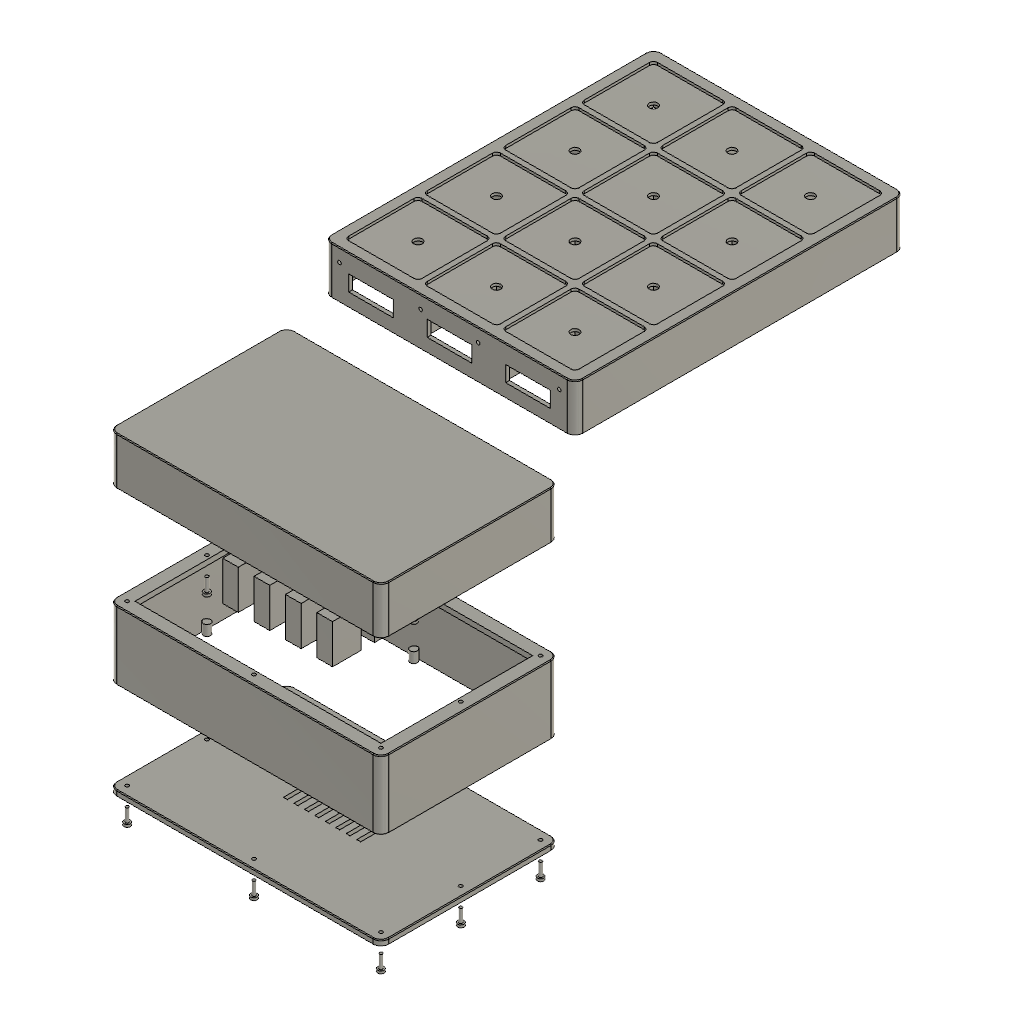
2026-11-06_BedPrototype_exploded (Autodesk Fusion 360 design; units mm, degrees)
part number: 2026-11-06-16-17-52-763
part number: 2026-11-06-16-17-53-532
part number: 2026-11-06-16-17-53-541
part number: 2026-11-06-16-17-56-764
part number: 2026-11-06-16-18-10-254
part number: 2026-11-06-16-18-27-251
part number: 2026-11-06-16-18-36-458
part number: 2026-11-06-16-18-36-601
part number: 2026-11-06-16-18-37-298
part number: 2026-11-06-16-18-38-009
part number: 2026-11-06-16-18-38-722
part number: 2026-11-06-16-18-39-449
part number: 2026-11-06-16-18-40-166
part number: 2026-11-06-16-18-41-052
part number: 2026-11-06-16-18-41-792
part number: 2026-11-06-16-18-42-542
part number: 2026-11-06-16-18-43-311
part number: 2026-11-06-16-18-44-069
part number: 2026-11-06-16-18-44-830
part number: 2026-11-06-16-18-45-611
part number: 2026-11-06-16-21-55-752
part number: 2026-11-06-16-21-56-338
part number: 2026-11-06-16-22-01-280
part number: 2026-11-06-16-22-06-008
part number: 2026-11-06-16-22-10-940
part number: 2026-11-06-16-22-16-295
part number: 2026-11-06-16-22-16-807
part number: 2026-11-06-16-22-21-639
part number: 2026-11-06-16-22-26-652
part number: 2026-11-06-16-22-31-892
part number: 2026-11-06-16-22-37-156
part number: 2026-11-06-16-22-42-135
part number: 2026-11-06-16-22-47-394
part number: 2026-11-06-16-22-53-084
part number: 2026-11-06-16-23-01-019
part number: 2026-11-06-16-23-01-608
part number: 2026-11-06-16-23-07-100
part number: 2026-11-06-16-23-12-774
part number: 2026-11-06-16-23-18-494
part number: 2026-11-06-16-23-24-293
part number: 2026-11-06-16-23-30-353
part number: 2026-11-06-16-23-36-101
part number: 2026-11-06-16-23-41-974
Autodesk Fusion 360 part; units mm, degrees
(part 1 of 3)
ref_plane "WorkPlane1" through (0, 0, 0) normal (0, 0, 1) x (1, 0, 0) in component "BedFrame_CellDeck"
sketch "DeckBlank_Sketch" plane through (0, 0, 0) normal (0, 0, 1) x (1, 0, 0) in component "BedFrame_CellDeck"
  line L0 (-96, -126) -> (96, -126)
  line L1 (96, -126) -> (96, 126)
  line L2 (96, 126) -> (-96, 126)
  line L3 (-96, 126) -> (-96, -126)
extrude "DeckBlank" add sketch "DeckBlank_Sketch" along normal blind 36 makes body 1 in component "BedFrame_CellDeck"
fillet "OuterCorner_R6" radius 6 4 edges at (-96, 126, 18) (96, 126, 18) (96, -126, 18) (-96, -126, 18) on bodies 1 in component "BedFrame_CellDeck"
ref_plane "WorkPlane2" through (0, 0, 0) normal (0, 0, 1) x (1, 0, 0) in component "BedFrame_CellDeck"
sketch "OpenUnderside_Sketch" plane through (0, 0, 0) normal (0, 0, 1) x (1, 0, 0) in component "BedFrame_CellDeck"
  line L0 (-93, -123) -> (93, -123)
  line L1 (93, -123) -> (93, 123)
  line L2 (93, 123) -> (-93, 123)
  line L3 (-93, 123) -> (-93, -123)
extrude "OpenUnderside" cut sketch "OpenUnderside_Sketch" along normal blind 32 bodies 1 in component "BedFrame_CellDeck"
ref_plane "WorkPlane3" through (0, 0, 0) normal (0, 0, 1) x (1, 0, 0) in component "BedFrame_CellDeck"
sketch "LongRib_0_Sketch" plane through (0, 0, 0) normal (0, 0, 1) x (1, 0, 0) in component "BedFrame_CellDeck"
  line L0 (-32, -123.1) -> (-28, -123.1)
  line L1 (-28, -123.1) -> (-28, 123.1)
  line L2 (-28, 123.1) -> (-32, 123.1)
  line L3 (-32, 123.1) -> (-32, -123.1)
extrude "LongRib_0" add sketch "LongRib_0_Sketch" along normal blind 32 bodies 1 in component "BedFrame_CellDeck"
ref_plane "WorkPlane4" through (0, 0, 0) normal (0, 0, 1) x (1, 0, 0) in component "BedFrame_CellDeck"
sketch "LongRib_1_Sketch" plane through (0, 0, 0) normal (0, 0, 1) x (1, 0, 0) in component "BedFrame_CellDeck"
  line L0 (28, -123.1) -> (32, -123.1)
  line L1 (32, -123.1) -> (32, 123.1)
  line L2 (32, 123.1) -> (28, 123.1)
  line L3 (28, 123.1) -> (28, -123.1)
extrude "LongRib_1" add sketch "LongRib_1_Sketch" along normal blind 32 bodies 1 in component "BedFrame_CellDeck"
ref_plane "WorkPlane5" through (0, 0, 0) normal (0, 0, 1) x (1, 0, 0) in component "BedFrame_CellDeck"
sketch "CrossRib_0_Sketch" plane through (0, 0, 0) normal (0, 0, 1) x (1, 0, 0) in component "BedFrame_CellDeck"
  line L0 (-93.1, 58) -> (93.1, 58)
  line L1 (93.1, 58) -> (93.1, 62)
  line L2 (93.1, 62) -> (-93.1, 62)
  line L3 (-93.1, 62) -> (-93.1, 58)
extrude "CrossRib_0" add sketch "CrossRib_0_Sketch" along normal blind 32 bodies 1 in component "BedFrame_CellDeck"
ref_plane "WorkPlane6" through (0, 0, 0) normal (0, 0, 1) x (1, 0, 0) in component "BedFrame_CellDeck"
sketch "CrossRib_1_Sketch" plane through (0, 0, 0) normal (0, 0, 1) x (1, 0, 0) in component "BedFrame_CellDeck"
  line L0 (-93.1, -2) -> (93.1, -2)
  line L1 (93.1, -2) -> (93.1, 2)
  line L2 (93.1, 2) -> (-93.1, 2)
  line L3 (-93.1, 2) -> (-93.1, -2)
extrude "CrossRib_1" add sketch "CrossRib_1_Sketch" along normal blind 32 bodies 1 in component "BedFrame_CellDeck"
ref_plane "WorkPlane7" through (0, 0, 0) normal (0, 0, 1) x (1, 0, 0) in component "BedFrame_CellDeck"
sketch "CrossRib_2_Sketch" plane through (0, 0, 0) normal (0, 0, 1) x (1, 0, 0) in component "BedFrame_CellDeck"
  line L0 (-93.1, -62) -> (93.1, -62)
  line L1 (93.1, -62) -> (93.1, -58)
  line L2 (93.1, -58) -> (-93.1, -58)
  line L3 (-93.1, -58) -> (-93.1, -62)
extrude "CrossRib_2" add sketch "CrossRib_2_Sketch" along normal blind 32 bodies 1 in component "BedFrame_CellDeck"
ref_plane "WorkPlane8" through (0, 0, 36) normal (0, 0, 1) x (1, 0, 0) in component "BedFrame_CellDeck"
sketch "Seat_A1_Sketch" plane through (0, 0, 36) normal (0, 0, 1) x (1, 0, 0) in component "BedFrame_CellDeck"
  line L0 (-88, 62) -> (-32, 62)
  line L1 (-32, 62) -> (-32, 118)
  line L2 (-32, 118) -> (-88, 118)
  line L3 (-88, 118) -> (-88, 62)
extrude "Seat_A1" cut sketch "Seat_A1_Sketch" against normal blind 2 bodies 1 in component "BedFrame_CellDeck"
ref_plane "WorkPlane9" through (0, 0, 34) normal (0, 0, 1) x (1, 0, 0) in component "BedFrame_CellDeck"
sketch "Port_A1_Sketch" plane through (0, 0, 34) normal (0, 0, 1) x (1, 0, 0) in component "BedFrame_CellDeck"
  circle A0 centre (-60, 90) radius 3.25
extrude "Port_A1" cut sketch "Port_A1_Sketch" against normal blind 2 bodies 1 in component "BedFrame_CellDeck"
ref_plane "WorkPlane10" through (0, 0, 36) normal (0, 0, 1) x (1, 0, 0) in component "BedFrame_CellDeck"
sketch "Seat_B1_Sketch" plane through (0, 0, 36) normal (0, 0, 1) x (1, 0, 0) in component "BedFrame_CellDeck"
  line L0 (-28, 62) -> (28, 62)
  line L1 (28, 62) -> (28, 118)
  line L2 (28, 118) -> (-28, 118)
  line L3 (-28, 118) -> (-28, 62)
extrude "Seat_B1" cut sketch "Seat_B1_Sketch" against normal blind 2 bodies 1 in component "BedFrame_CellDeck"
ref_plane "WorkPlane11" through (0, 0, 34) normal (0, 0, 1) x (1, 0, 0) in component "BedFrame_CellDeck"
sketch "Port_B1_Sketch" plane through (0, 0, 34) normal (0, 0, 1) x (1, 0, 0) in component "BedFrame_CellDeck"
  circle A0 centre (0, 90) radius 3.25
extrude "Port_B1" cut sketch "Port_B1_Sketch" against normal blind 2 bodies 1 in component "BedFrame_CellDeck"
ref_plane "WorkPlane12" through (0, 0, 36) normal (0, 0, 1) x (1, 0, 0) in component "BedFrame_CellDeck"
sketch "Seat_C1_Sketch" plane through (0, 0, 36) normal (0, 0, 1) x (1, 0, 0) in component "BedFrame_CellDeck"
  line L0 (32, 62) -> (88, 62)
  line L1 (88, 62) -> (88, 118)
  line L2 (88, 118) -> (32, 118)
  line L3 (32, 118) -> (32, 62)
extrude "Seat_C1" cut sketch "Seat_C1_Sketch" against normal blind 2 bodies 1 in component "BedFrame_CellDeck"
ref_plane "WorkPlane13" through (0, 0, 34) normal (0, 0, 1) x (1, 0, 0) in component "BedFrame_CellDeck"
sketch "Port_C1_Sketch" plane through (0, 0, 34) normal (0, 0, 1) x (1, 0, 0) in component "BedFrame_CellDeck"
  circle A0 centre (60, 90) radius 3.25
extrude "Port_C1" cut sketch "Port_C1_Sketch" against normal blind 2 bodies 1 in component "BedFrame_CellDeck"
ref_plane "WorkPlane14" through (0, 0, 36) normal (0, 0, 1) x (1, 0, 0) in component "BedFrame_CellDeck"
sketch "Seat_A2_Sketch" plane through (0, 0, 36) normal (0, 0, 1) x (1, 0, 0) in component "BedFrame_CellDeck"
  line L0 (-88, 2) -> (-32, 2)
  line L1 (-32, 2) -> (-32, 58)
  line L2 (-32, 58) -> (-88, 58)
  line L3 (-88, 58) -> (-88, 2)
extrude "Seat_A2" cut sketch "Seat_A2_Sketch" against normal blind 2 bodies 1 in component "BedFrame_CellDeck"
ref_plane "WorkPlane15" through (0, 0, 34) normal (0, 0, 1) x (1, 0, 0) in component "BedFrame_CellDeck"
sketch "Port_A2_Sketch" plane through (0, 0, 34) normal (0, 0, 1) x (1, 0, 0) in component "BedFrame_CellDeck"
  circle A0 centre (-60, 30) radius 3.25
extrude "Port_A2" cut sketch "Port_A2_Sketch" against normal blind 2 bodies 1 in component "BedFrame_CellDeck"
ref_plane "WorkPlane16" through (0, 0, 36) normal (0, 0, 1) x (1, 0, 0) in component "BedFrame_CellDeck"
sketch "Seat_B2_Sketch" plane through (0, 0, 36) normal (0, 0, 1) x (1, 0, 0) in component "BedFrame_CellDeck"
  line L0 (-28, 2) -> (28, 2)
  line L1 (28, 2) -> (28, 58)
  line L2 (28, 58) -> (-28, 58)
  line L3 (-28, 58) -> (-28, 2)
extrude "Seat_B2" cut sketch "Seat_B2_Sketch" against normal blind 2 bodies 1 in component "BedFrame_CellDeck"
ref_plane "WorkPlane17" through (0, 0, 34) normal (0, 0, 1) x (1, 0, 0) in component "BedFrame_CellDeck"
sketch "Port_B2_Sketch" plane through (0, 0, 34) normal (0, 0, 1) x (1, 0, 0) in component "BedFrame_CellDeck"
  circle A0 centre (0, 30) radius 3.25
extrude "Port_B2" cut sketch "Port_B2_Sketch" against normal blind 2 bodies 1 in component "BedFrame_CellDeck"
ref_plane "WorkPlane18" through (0, 0, 36) normal (0, 0, 1) x (1, 0, 0) in component "BedFrame_CellDeck"
sketch "Seat_C2_Sketch" plane through (0, 0, 36) normal (0, 0, 1) x (1, 0, 0) in component "BedFrame_CellDeck"
  line L0 (32, 2) -> (88, 2)
  line L1 (88, 2) -> (88, 58)
  line L2 (88, 58) -> (32, 58)
  line L3 (32, 58) -> (32, 2)
extrude "Seat_C2" cut sketch "Seat_C2_Sketch" against normal blind 2 bodies 1 in component "BedFrame_CellDeck"
ref_plane "WorkPlane19" through (0, 0, 34) normal (0, 0, 1) x (1, 0, 0) in component "BedFrame_CellDeck"
sketch "Port_C2_Sketch" plane through (0, 0, 34) normal (0, 0, 1) x (1, 0, 0) in component "BedFrame_CellDeck"
  circle A0 centre (60, 30) radius 3.25
extrude "Port_C2" cut sketch "Port_C2_Sketch" against normal blind 2 bodies 1 in component "BedFrame_CellDeck"
ref_plane "WorkPlane20" through (0, 0, 36) normal (0, 0, 1) x (1, 0, 0) in component "BedFrame_CellDeck"
sketch "Seat_A3_Sketch" plane through (0, 0, 36) normal (0, 0, 1) x (1, 0, 0) in component "BedFrame_CellDeck"
  line L0 (-88, -58) -> (-32, -58)
  line L1 (-32, -58) -> (-32, -2)
  line L2 (-32, -2) -> (-88, -2)
  line L3 (-88, -2) -> (-88, -58)
extrude "Seat_A3" cut sketch "Seat_A3_Sketch" against normal blind 2 bodies 1 in component "BedFrame_CellDeck"
ref_plane "WorkPlane21" through (0, 0, 34) normal (0, 0, 1) x (1, 0, 0) in component "BedFrame_CellDeck"
sketch "Port_A3_Sketch" plane through (0, 0, 34) normal (0, 0, 1) x (1, 0, 0) in component "BedFrame_CellDeck"
  circle A0 centre (-60, -30) radius 3.25
extrude "Port_A3" cut sketch "Port_A3_Sketch" against normal blind 2 bodies 1 in component "BedFrame_CellDeck"
ref_plane "WorkPlane22" through (0, 0, 36) normal (0, 0, 1) x (1, 0, 0) in component "BedFrame_CellDeck"
sketch "Seat_B3_Sketch" plane through (0, 0, 36) normal (0, 0, 1) x (1, 0, 0) in component "BedFrame_CellDeck"
  line L0 (-28, -58) -> (28, -58)
  line L1 (28, -58) -> (28, -2)
  line L2 (28, -2) -> (-28, -2)
  line L3 (-28, -2) -> (-28, -58)
extrude "Seat_B3" cut sketch "Seat_B3_Sketch" against normal blind 2 bodies 1 in component "BedFrame_CellDeck"
ref_plane "WorkPlane23" through (0, 0, 34) normal (0, 0, 1) x (1, 0, 0) in component "BedFrame_CellDeck"
sketch "Port_B3_Sketch" plane through (0, 0, 34) normal (0, 0, 1) x (1, 0, 0) in component "BedFrame_CellDeck"
  circle A0 centre (0, -30) radius 3.25
extrude "Port_B3" cut sketch "Port_B3_Sketch" against normal blind 2 bodies 1 in component "BedFrame_CellDeck"
ref_plane "WorkPlane24" through (0, 0, 36) normal (0, 0, 1) x (1, 0, 0) in component "BedFrame_CellDeck"
sketch "Seat_C3_Sketch" plane through (0, 0, 36) normal (0, 0, 1) x (1, 0, 0) in component "BedFrame_CellDeck"
  line L0 (32, -58) -> (88, -58)
  line L1 (88, -58) -> (88, -2)
  line L2 (88, -2) -> (32, -2)
  line L3 (32, -2) -> (32, -58)
extrude "Seat_C3" cut sketch "Seat_C3_Sketch" against normal blind 2 bodies 1 in component "BedFrame_CellDeck"
ref_plane "WorkPlane25" through (0, 0, 34) normal (0, 0, 1) x (1, 0, 0) in component "BedFrame_CellDeck"
sketch "Port_C3_Sketch" plane through (0, 0, 34) normal (0, 0, 1) x (1, 0, 0) in component "BedFrame_CellDeck"
  circle A0 centre (60, -30) radius 3.25
extrude "Port_C3" cut sketch "Port_C3_Sketch" against normal blind 2 bodies 1 in component "BedFrame_CellDeck"
ref_plane "WorkPlane26" through (0, 0, 36) normal (0, 0, 1) x (1, 0, 0) in component "BedFrame_CellDeck"
sketch "Seat_A4_Sketch" plane through (0, 0, 36) normal (0, 0, 1) x (1, 0, 0) in component "BedFrame_CellDeck"
  line L0 (-88, -118) -> (-32, -118)
  line L1 (-32, -118) -> (-32, -62)
  line L2 (-32, -62) -> (-88, -62)
  line L3 (-88, -62) -> (-88, -118)
extrude "Seat_A4" cut sketch "Seat_A4_Sketch" against normal blind 2 bodies 1 in component "BedFrame_CellDeck"
ref_plane "WorkPlane27" through (0, 0, 34) normal (0, 0, 1) x (1, 0, 0) in component "BedFrame_CellDeck"
sketch "Port_A4_Sketch" plane through (0, 0, 34) normal (0, 0, 1) x (1, 0, 0) in component "BedFrame_CellDeck"
  circle A0 centre (-60, -90) radius 3.25
extrude "Port_A4" cut sketch "Port_A4_Sketch" against normal blind 2 bodies 1 in component "BedFrame_CellDeck"
ref_plane "WorkPlane28" through (0, 0, 36) normal (0, 0, 1) x (1, 0, 0) in component "BedFrame_CellDeck"
sketch "Seat_B4_Sketch" plane through (0, 0, 36) normal (0, 0, 1) x (1, 0, 0) in component "BedFrame_CellDeck"
  line L0 (-28, -118) -> (28, -118)
  line L1 (28, -118) -> (28, -62)
  line L2 (28, -62) -> (-28, -62)
  line L3 (-28, -62) -> (-28, -118)
extrude "Seat_B4" cut sketch "Seat_B4_Sketch" against normal blind 2 bodies 1 in component "BedFrame_CellDeck"
ref_plane "WorkPlane29" through (0, 0, 34) normal (0, 0, 1) x (1, 0, 0) in component "BedFrame_CellDeck"
sketch "Port_B4_Sketch" plane through (0, 0, 34) normal (0, 0, 1) x (1, 0, 0) in component "BedFrame_CellDeck"
  circle A0 centre (0, -90) radius 3.25
extrude "Port_B4" cut sketch "Port_B4_Sketch" against normal blind 2 bodies 1 in component "BedFrame_CellDeck"
ref_plane "WorkPlane30" through (0, 0, 36) normal (0, 0, 1) x (1, 0, 0) in component "BedFrame_CellDeck"
sketch "Seat_C4_Sketch" plane through (0, 0, 36) normal (0, 0, 1) x (1, 0, 0) in component "BedFrame_CellDeck"
  line L0 (32, -118) -> (88, -118)
  line L1 (88, -118) -> (88, -62)
  line L2 (88, -62) -> (32, -62)
  line L3 (32, -62) -> (32, -118)
extrude "Seat_C4" cut sketch "Seat_C4_Sketch" against normal blind 2 bodies 1 in component "BedFrame_CellDeck"
ref_plane "WorkPlane31" through (0, 0, 34) normal (0, 0, 1) x (1, 0, 0) in component "BedFrame_CellDeck"
sketch "Port_C4_Sketch" plane through (0, 0, 34) normal (0, 0, 1) x (1, 0, 0) in component "BedFrame_CellDeck"
  circle A0 centre (60, -90) radius 3.25
extrude "Port_C4" cut sketch "Port_C4_Sketch" against normal blind 2 bodies 1 in component "BedFrame_CellDeck"
ref_plane "WorkPlane32" through (0, 0, 10) normal (0, 0, 1) x (1, 0, 0) in component "BedFrame_CellDeck"
sketch "TubeBundle_0_Sketch" plane through (0, 0, 10) normal (0, 0, 1) x (1, 0, 0) in component "BedFrame_CellDeck"
  line L0 (-77, -126.1) -> (-43, -126.1)
  line L1 (-43, -126.1) -> (-43, 122.9)
  line L2 (-43, 122.9) -> (-77, 122.9)
  line L3 (-77, 122.9) -> (-77, -126.1)
extrude "TubeBundle_0" cut sketch "TubeBundle_0_Sketch" along normal blind 12 bodies 1 in component "BedFrame_CellDeck"
ref_plane "WorkPlane33" through (0, 0, 10) normal (0, 0, 1) x (1, 0, 0) in component "BedFrame_CellDeck"
sketch "TubeBundle_1_Sketch" plane through (0, 0, 10) normal (0, 0, 1) x (1, 0, 0) in component "BedFrame_CellDeck"
  line L0 (-17, -126.1) -> (17, -126.1)
  line L1 (17, -126.1) -> (17, 122.9)
  line L2 (17, 122.9) -> (-17, 122.9)
  line L3 (-17, 122.9) -> (-17, -126.1)
extrude "TubeBundle_1" cut sketch "TubeBundle_1_Sketch" along normal blind 12 bodies 1 in component "BedFrame_CellDeck"
ref_plane "WorkPlane34" through (0, 0, 10) normal (0, 0, 1) x (1, 0, 0) in component "BedFrame_CellDeck"
sketch "TubeBundle_2_Sketch" plane through (0, 0, 10) normal (0, 0, 1) x (1, 0, 0) in component "BedFrame_CellDeck"
  line L0 (43, -126.1) -> (77, -126.1)
  line L1 (77, -126.1) -> (77, 122.9)
  line L2 (77, 122.9) -> (43, 122.9)
  line L3 (43, 122.9) -> (43, -126.1)
extrude "TubeBundle_2" cut sketch "TubeBundle_2_Sketch" along normal blind 12 bodies 1 in component "BedFrame_CellDeck"
ref_plane "WorkPlane35" through (0, -126.1, 0) normal (0, 1, 0) x (0, 0, 1) in component "BedFrame_CellDeck"
sketch "ServiceClearance_0_Sketch" plane through (0, -126.1, 0) normal (0, 1, 0) x (1, 0, 0) in component "BedFrame_CellDeck"
  circle A0 centre (-84, -26) radius 1.35
extrude "ServiceClearance_0" cut sketch "ServiceClearance_0_Sketch" along normal blind 3.2 bodies 1 in component "BedFrame_CellDeck"
ref_plane "WorkPlane36" through (0, -126.1, 0) normal (0, 1, 0) x (0, 0, 1) in component "BedFrame_CellDeck"
sketch "ServiceClearance_1_Sketch" plane through (0, -126.1, 0) normal (0, 1, 0) x (1, 0, 0) in component "BedFrame_CellDeck"
  circle A0 centre (-22, -26) radius 1.35
extrude "ServiceClearance_1" cut sketch "ServiceClearance_1_Sketch" along normal blind 3.2 bodies 1 in component "BedFrame_CellDeck"
ref_plane "WorkPlane37" through (0, -126.1, 0) normal (0, 1, 0) x (0, 0, 1) in component "BedFrame_CellDeck"
sketch "ServiceClearance_2_Sketch" plane through (0, -126.1, 0) normal (0, 1, 0) x (1, 0, 0) in component "BedFrame_CellDeck"
  circle A0 centre (22, -26) radius 1.35
extrude "ServiceClearance_2" cut sketch "ServiceClearance_2_Sketch" along normal blind 3.2 bodies 1 in component "BedFrame_CellDeck"
ref_plane "WorkPlane38" through (0, -126.1, 0) normal (0, 1, 0) x (0, 0, 1) in component "BedFrame_CellDeck"
sketch "ServiceClearance_3_Sketch" plane through (0, -126.1, 0) normal (0, 1, 0) x (1, 0, 0) in component "BedFrame_CellDeck"
  circle A0 centre (84, -26) radius 1.35
extrude "ServiceClearance_3" cut sketch "ServiceClearance_3_Sketch" along normal blind 3.2 bodies 1 in component "BedFrame_CellDeck"
fillet "RoundedCellSeats" radius 3 48 edges at (88, -118, 35) (32, -118, 35) (88, -62, 35) (32, -62, 35) (28, -118, 35) (-28, -118, 35) (28, -62, 35) (-28, -62, 35) (-32, -118, 35) (-88, -118, 35) (-32, -62, 35) (-88, -62, 35) (88, -58, 35) (32, -58, 35) (88, -2, 35) (32, -2, 35) (28, -58, 35) (-28, -58, 35) (28, -2, 35) (-28, -2, 35) (-32, -58, 35) (-88, -58, 35) (-32, -2, 35) (-88, -2, 35) (88, 2, 35) (32, 2, 35) (88, 58, 35) (32, 58, 35) (28, 2, 35) (-28, 2, 35) (28, 58, 35) (-28, 58, 35) (-32, 2, 35) (-88, 2, 35) (-32, 58, 35) (-88, 58, 35) (88, 62, 35) (32, 62, 35) (88, 118, 35) (32, 118, 35) (28, 62, 35) (-28, 62, 35) (28, 118, 35) (-28, 118, 35) (-32, 62, 35) (-88, 62, 35) (-32, 118, 35) (-88, 118, 35) on bodies 1 in component "BedFrame_CellDeck"
fillet "OuterTopEdgeSoftening" radius 0.6 8 edges at (-94.2426, -124.2426, 36) (-96, 0, 36) (0, -126, 36) (94.2426, -124.2426, 36) (96, 0, 36) (94.2426, 124.2426, 36) (0, 126, 36) (-94.2426, 124.2426, 36) on bodies 1 in component "BedFrame_CellDeck"
ref_plane "WorkPlane1" through (0, 0, 0) normal (0, 0, 1) x (1, 0, 0) in component "BedFrame_ServiceDeck"
sketch "ServiceBlank_Sketch" plane through (0, 0, 0) normal (0, 0, 1) x (1, 0, 0) in component "BedFrame_ServiceDeck"
  line L0 (-104, -262.3) -> (104, -262.3)
  line L1 (104, -262.3) -> (104, -126.3)
  line L2 (104, -126.3) -> (-104, -126.3)
  line L3 (-104, -126.3) -> (-104, -262.3)
extrude "ServiceBlank" add sketch "ServiceBlank_Sketch" along normal blind 36 separate body makes body 2 in component "BedFrame_ServiceDeck"
fillet "ServiceCorners" radius 6 4 edges at (-104, -126.3, 18) (104, -126.3, 18) (104, -262.3, 18) (-104, -262.3, 18) on bodies 2 in component "BedFrame_ServiceDeck"
ref_plane "WorkPlane2" through (0, 0, 0) normal (0, 0, 1) x (1, 0, 0) in component "BedFrame_ServiceDeck"
sketch "ServiceCavity_Sketch" plane through (0, 0, 0) normal (0, 0, 1) x (1, 0, 0) in component "BedFrame_ServiceDeck"
  line L0 (-100, -258.3) -> (100, -258.3)
  line L1 (100, -258.3) -> (100, -130.3)
  line L2 (100, -130.3) -> (-100, -130.3)
  line L3 (-100, -130.3) -> (-100, -258.3)
extrude "ServiceCavity" cut sketch "ServiceCavity_Sketch" along normal blind 32 bodies 2 in component "BedFrame_ServiceDeck"
ref_plane "WorkPlane3" through (0, 0, 0) normal (0, 0, 1) x (1, 0, 0) in component "BedFrame_ServiceDeck"
sketch "LowerFlangeBlank_Sketch" plane through (0, 0, 0) normal (0, 0, 1) x (1, 0, 0) in component "BedFrame_ServiceDeck"
  line L0 (-100.1, -258.4) -> (100.1, -258.4)
  line L1 (100.1, -258.4) -> (100.1, -130.2)
  line L2 (100.1, -130.2) -> (-100.1, -130.2)
  line L3 (-100.1, -130.2) -> (-100.1, -258.4)
extrude "LowerFlangeBlank" add sketch "LowerFlangeBlank_Sketch" along normal blind 4 bodies 2 in component "BedFrame_ServiceDeck"
ref_plane "WorkPlane4" through (0, 0, -0.1) normal (0, 0, 1) x (1, 0, 0) in component "BedFrame_ServiceDeck"
sketch "LowerFlangeOpening_Sketch" plane through (0, 0, -0.1) normal (0, 0, 1) x (1, 0, 0) in component "BedFrame_ServiceDeck"
  line L0 (-94, -252.3) -> (94, -252.3)
  line L1 (94, -252.3) -> (94, -136.3)
  line L2 (94, -136.3) -> (-94, -136.3)
  line L3 (-94, -136.3) -> (-94, -252.3)
extrude "LowerFlangeOpening" cut sketch "LowerFlangeOpening_Sketch" along normal blind 4.2 bodies 2 in component "BedFrame_ServiceDeck"
ref_plane "WorkPlane5" through (0, 0, 21) normal (0, 0, 1) x (1, 0, 0) in component "BedFrame_ServiceDeck"
sketch "CellJointPad_0_Sketch" plane through (0, 0, 21) normal (0, 0, 1) x (1, 0, 0) in component "BedFrame_ServiceDeck"
  line L0 (-89, -134.3) -> (-79, -134.3)
  line L1 (-79, -134.3) -> (-79, -126.3)
  line L2 (-79, -126.3) -> (-89, -126.3)
  line L3 (-89, -126.3) -> (-89, -134.3)
extrude "CellJointPad_0" add sketch "CellJointPad_0_Sketch" along normal blind 10 bodies 2 in component "BedFrame_ServiceDeck"
ref_plane "WorkPlane6" through (0, -126.2, 0) normal (0, 1, 0) x (0, 0, 1) in component "BedFrame_ServiceDeck"
sketch "CellJointPilot_0_Sketch" plane through (0, -126.2, 0) normal (0, 1, 0) x (1, 0, 0) in component "BedFrame_ServiceDeck"
  circle A0 centre (-84, -26) radius 1.05
extrude "CellJointPilot_0" cut sketch "CellJointPilot_0_Sketch" against normal blind 7.1 bodies 2 in component "BedFrame_ServiceDeck"
ref_plane "WorkPlane7" through (0, 0, 21) normal (0, 0, 1) x (1, 0, 0) in component "BedFrame_ServiceDeck"
sketch "CellJointPad_1_Sketch" plane through (0, 0, 21) normal (0, 0, 1) x (1, 0, 0) in component "BedFrame_ServiceDeck"
  line L0 (-27, -134.3) -> (-17, -134.3)
  line L1 (-17, -134.3) -> (-17, -126.3)
  line L2 (-17, -126.3) -> (-27, -126.3)
  line L3 (-27, -126.3) -> (-27, -134.3)
extrude "CellJointPad_1" add sketch "CellJointPad_1_Sketch" along normal blind 10 bodies 2 in component "BedFrame_ServiceDeck"
ref_plane "WorkPlane8" through (0, -126.2, 0) normal (0, 1, 0) x (0, 0, 1) in component "BedFrame_ServiceDeck"
sketch "CellJointPilot_1_Sketch" plane through (0, -126.2, 0) normal (0, 1, 0) x (1, 0, 0) in component "BedFrame_ServiceDeck"
  circle A0 centre (-22, -26) radius 1.05
extrude "CellJointPilot_1" cut sketch "CellJointPilot_1_Sketch" against normal blind 7.1 bodies 2 in component "BedFrame_ServiceDeck"
ref_plane "WorkPlane9" through (0, 0, 21) normal (0, 0, 1) x (1, 0, 0) in component "BedFrame_ServiceDeck"
sketch "CellJointPad_2_Sketch" plane through (0, 0, 21) normal (0, 0, 1) x (1, 0, 0) in component "BedFrame_ServiceDeck"
  line L0 (17, -134.3) -> (27, -134.3)
  line L1 (27, -134.3) -> (27, -126.3)
  line L2 (27, -126.3) -> (17, -126.3)
  line L3 (17, -126.3) -> (17, -134.3)
extrude "CellJointPad_2" add sketch "CellJointPad_2_Sketch" along normal blind 10 bodies 2 in component "BedFrame_ServiceDeck"
ref_plane "WorkPlane10" through (0, -126.2, 0) normal (0, 1, 0) x (0, 0, 1) in component "BedFrame_ServiceDeck"
sketch "CellJointPilot_2_Sketch" plane through (0, -126.2, 0) normal (0, 1, 0) x (1, 0, 0) in component "BedFrame_ServiceDeck"
  circle A0 centre (22, -26) radius 1.05
extrude "CellJointPilot_2" cut sketch "CellJointPilot_2_Sketch" against normal blind 7.1 bodies 2 in component "BedFrame_ServiceDeck"
ref_plane "WorkPlane11" through (0, 0, 21) normal (0, 0, 1) x (1, 0, 0) in component "BedFrame_ServiceDeck"
sketch "CellJointPad_3_Sketch" plane through (0, 0, 21) normal (0, 0, 1) x (1, 0, 0) in component "BedFrame_ServiceDeck"
  line L0 (79, -134.3) -> (89, -134.3)
  line L1 (89, -134.3) -> (89, -126.3)
  line L2 (89, -126.3) -> (79, -126.3)
  line L3 (79, -126.3) -> (79, -134.3)
extrude "CellJointPad_3" add sketch "CellJointPad_3_Sketch" along normal blind 10 bodies 2 in component "BedFrame_ServiceDeck"
ref_plane "WorkPlane12" through (0, -126.2, 0) normal (0, 1, 0) x (0, 0, 1) in component "BedFrame_ServiceDeck"
sketch "CellJointPilot_3_Sketch" plane through (0, -126.2, 0) normal (0, 1, 0) x (1, 0, 0) in component "BedFrame_ServiceDeck"
  circle A0 centre (84, -26) radius 1.05
extrude "CellJointPilot_3" cut sketch "CellJointPilot_3_Sketch" against normal blind 7.1 bodies 2 in component "BedFrame_ServiceDeck"
ref_plane "WorkPlane13" through (0, 0, 10) normal (0, 0, 1) x (1, 0, 0) in component "BedFrame_ServiceDeck"
sketch "Bulkhead_0_Sketch" plane through (0, 0, 10) normal (0, 0, 1) x (1, 0, 0) in component "BedFrame_ServiceDeck"
  line L0 (-77, -130.4) -> (-43, -130.4)
  line L1 (-43, -130.4) -> (-43, -126.2)
  line L2 (-43, -126.2) -> (-77, -126.2)
  line L3 (-77, -126.2) -> (-77, -130.4)
extrude "Bulkhead_0" cut sketch "Bulkhead_0_Sketch" along normal blind 12 bodies 2 in component "BedFrame_ServiceDeck"
ref_plane "WorkPlane14" through (0, 0, 10) normal (0, 0, 1) x (1, 0, 0) in component "BedFrame_ServiceDeck"
sketch "Bulkhead_1_Sketch" plane through (0, 0, 10) normal (0, 0, 1) x (1, 0, 0) in component "BedFrame_ServiceDeck"
  line L0 (-17, -130.4) -> (17, -130.4)
  line L1 (17, -130.4) -> (17, -126.2)
  line L2 (17, -126.2) -> (-17, -126.2)
  line L3 (-17, -126.2) -> (-17, -130.4)
extrude "Bulkhead_1" cut sketch "Bulkhead_1_Sketch" along normal blind 12 bodies 2 in component "BedFrame_ServiceDeck"
ref_plane "WorkPlane15" through (0, 0, 10) normal (0, 0, 1) x (1, 0, 0) in component "BedFrame_ServiceDeck"
sketch "Bulkhead_2_Sketch" plane through (0, 0, 10) normal (0, 0, 1) x (1, 0, 0) in component "BedFrame_ServiceDeck"
  line L0 (43, -130.4) -> (77, -130.4)
  line L1 (77, -130.4) -> (77, -126.2)
  line L2 (77, -126.2) -> (43, -126.2)
  line L3 (43, -126.2) -> (43, -130.4)
extrude "Bulkhead_2" cut sketch "Bulkhead_2_Sketch" along normal blind 12 bodies 2 in component "BedFrame_ServiceDeck"
ref_plane "WorkPlane16" through (0, 0, 0) normal (0, 0, 1) x (1, 0, 0) in component "BedFrame_ServiceDeck"
sketch "RimReceiver_0_Sketch" plane through (0, 0, 0) normal (0, 0, 1) x (1, 0, 0) in component "BedFrame_ServiceDeck"
  circle A0 centre (-97, -255.3) radius 2.75
extrude "RimReceiver_0" add sketch "RimReceiver_0_Sketch" along normal blind 8 bodies 2 in component "BedFrame_ServiceDeck"
ref_plane "WorkPlane17" through (0, 0, -0.1) normal (0, 0, 1) x (1, 0, 0) in component "BedFrame_ServiceDeck"
sketch "RimPilot_0_Sketch" plane through (0, 0, -0.1) normal (0, 0, 1) x (1, 0, 0) in component "BedFrame_ServiceDeck"
  circle A0 centre (-97, -255.3) radius 1.05
extrude "RimPilot_0" cut sketch "RimPilot_0_Sketch" along normal blind 7.1 bodies 2 in component "BedFrame_ServiceDeck"
ref_plane "WorkPlane18" through (0, 0, 0) normal (0, 0, 1) x (1, 0, 0) in component "BedFrame_ServiceDeck"
sketch "RimReceiver_1_Sketch" plane through (0, 0, 0) normal (0, 0, 1) x (1, 0, 0) in component "BedFrame_ServiceDeck"
  circle A0 centre (0, -255.3) radius 2.75
extrude "RimReceiver_1" add sketch "RimReceiver_1_Sketch" along normal blind 8 bodies 2 in component "BedFrame_ServiceDeck"
ref_plane "WorkPlane19" through (0, 0, -0.1) normal (0, 0, 1) x (1, 0, 0) in component "BedFrame_ServiceDeck"
sketch "RimPilot_1_Sketch" plane through (0, 0, -0.1) normal (0, 0, 1) x (1, 0, 0) in component "BedFrame_ServiceDeck"
  circle A0 centre (0, -255.3) radius 1.05
extrude "RimPilot_1" cut sketch "RimPilot_1_Sketch" along normal blind 7.1 bodies 2 in component "BedFrame_ServiceDeck"
ref_plane "WorkPlane20" through (0, 0, 0) normal (0, 0, 1) x (1, 0, 0) in component "BedFrame_ServiceDeck"
sketch "RimReceiver_2_Sketch" plane through (0, 0, 0) normal (0, 0, 1) x (1, 0, 0) in component "BedFrame_ServiceDeck"
  circle A0 centre (97, -255.3) radius 2.75
extrude "RimReceiver_2" add sketch "RimReceiver_2_Sketch" along normal blind 8 bodies 2 in component "BedFrame_ServiceDeck"
ref_plane "WorkPlane21" through (0, 0, -0.1) normal (0, 0, 1) x (1, 0, 0) in component "BedFrame_ServiceDeck"
sketch "RimPilot_2_Sketch" plane through (0, 0, -0.1) normal (0, 0, 1) x (1, 0, 0) in component "BedFrame_ServiceDeck"
  circle A0 centre (97, -255.3) radius 1.05
extrude "RimPilot_2" cut sketch "RimPilot_2_Sketch" along normal blind 7.1 bodies 2 in component "BedFrame_ServiceDeck"
ref_plane "WorkPlane22" through (0, 0, 0) normal (0, 0, 1) x (1, 0, 0) in component "BedFrame_ServiceDeck"
sketch "RimReceiver_3_Sketch" plane through (0, 0, 0) normal (0, 0, 1) x (1, 0, 0) in component "BedFrame_ServiceDeck"
  circle A0 centre (-97, -194.3) radius 2.75
extrude "RimReceiver_3" add sketch "RimReceiver_3_Sketch" along normal blind 8 bodies 2 in component "BedFrame_ServiceDeck"
ref_plane "WorkPlane23" through (0, 0, -0.1) normal (0, 0, 1) x (1, 0, 0) in component "BedFrame_ServiceDeck"
sketch "RimPilot_3_Sketch" plane through (0, 0, -0.1) normal (0, 0, 1) x (1, 0, 0) in component "BedFrame_ServiceDeck"
  circle A0 centre (-97, -194.3) radius 1.05
extrude "RimPilot_3" cut sketch "RimPilot_3_Sketch" along normal blind 7.1 bodies 2 in component "BedFrame_ServiceDeck"
ref_plane "WorkPlane24" through (0, 0, 0) normal (0, 0, 1) x (1, 0, 0) in component "BedFrame_ServiceDeck"
sketch "RimReceiver_4_Sketch" plane through (0, 0, 0) normal (0, 0, 1) x (1, 0, 0) in component "BedFrame_ServiceDeck"
  circle A0 centre (97, -194.3) radius 2.75
extrude "RimReceiver_4" add sketch "RimReceiver_4_Sketch" along normal blind 8 bodies 2 in component "BedFrame_ServiceDeck"
ref_plane "WorkPlane25" through (0, 0, -0.1) normal (0, 0, 1) x (1, 0, 0) in component "BedFrame_ServiceDeck"
sketch "RimPilot_4_Sketch" plane through (0, 0, -0.1) normal (0, 0, 1) x (1, 0, 0) in component "BedFrame_ServiceDeck"
  circle A0 centre (97, -194.3) radius 1.05
extrude "RimPilot_4" cut sketch "RimPilot_4_Sketch" along normal blind 7.1 bodies 2 in component "BedFrame_ServiceDeck"
ref_plane "WorkPlane26" through (0, 0, 0) normal (0, 0, 1) x (1, 0, 0) in component "BedFrame_ServiceDeck"
sketch "RimReceiver_5_Sketch" plane through (0, 0, 0) normal (0, 0, 1) x (1, 0, 0) in component "BedFrame_ServiceDeck"
  circle A0 centre (-97, -133.3) radius 2.75
extrude "RimReceiver_5" add sketch "RimReceiver_5_Sketch" along normal blind 8 bodies 2 in component "BedFrame_ServiceDeck"
ref_plane "WorkPlane27" through (0, 0, -0.1) normal (0, 0, 1) x (1, 0, 0) in component "BedFrame_ServiceDeck"
sketch "RimPilot_5_Sketch" plane through (0, 0, -0.1) normal (0, 0, 1) x (1, 0, 0) in component "BedFrame_ServiceDeck"
  circle A0 centre (-97, -133.3) radius 1.05
extrude "RimPilot_5" cut sketch "RimPilot_5_Sketch" along normal blind 7.1 bodies 2 in component "BedFrame_ServiceDeck"
ref_plane "WorkPlane28" through (0, 0, 0) normal (0, 0, 1) x (1, 0, 0) in component "BedFrame_ServiceDeck"
sketch "RimReceiver_6_Sketch" plane through (0, 0, 0) normal (0, 0, 1) x (1, 0, 0) in component "BedFrame_ServiceDeck"
  circle A0 centre (0, -133.3) radius 2.75
extrude "RimReceiver_6" add sketch "RimReceiver_6_Sketch" along normal blind 8 bodies 2 in component "BedFrame_ServiceDeck"
ref_plane "WorkPlane29" through (0, 0, -0.1) normal (0, 0, 1) x (1, 0, 0) in component "BedFrame_ServiceDeck"
sketch "RimPilot_6_Sketch" plane through (0, 0, -0.1) normal (0, 0, 1) x (1, 0, 0) in component "BedFrame_ServiceDeck"
  circle A0 centre (0, -133.3) radius 1.05
extrude "RimPilot_6" cut sketch "RimPilot_6_Sketch" along normal blind 7.1 bodies 2 in component "BedFrame_ServiceDeck"
ref_plane "WorkPlane30" through (0, 0, 0) normal (0, 0, 1) x (1, 0, 0) in component "BedFrame_ServiceDeck"
sketch "RimReceiver_7_Sketch" plane through (0, 0, 0) normal (0, 0, 1) x (1, 0, 0) in component "BedFrame_ServiceDeck"
  circle A0 centre (97, -133.3) radius 2.75
extrude "RimReceiver_7" add sketch "RimReceiver_7_Sketch" along normal blind 8 bodies 2 in component "BedFrame_ServiceDeck"
ref_plane "WorkPlane31" through (0, 0, -0.1) normal (0, 0, 1) x (1, 0, 0) in component "BedFrame_ServiceDeck"
sketch "RimPilot_7_Sketch" plane through (0, 0, -0.1) normal (0, 0, 1) x (1, 0, 0) in component "BedFrame_ServiceDeck"
  circle A0 centre (97, -133.3) radius 1.05
extrude "RimPilot_7" cut sketch "RimPilot_7_Sketch" along normal blind 7.1 bodies 2 in component "BedFrame_ServiceDeck"
ref_plane "WorkPlane32" through (0, 0, 22) normal (0, 0, 1) x (1, 0, 0) in component "BedFrame_ServiceDeck"
sketch "ValveRail_A1_-1_Sketch" plane through (0, 0, 22) normal (0, 0, 1) x (1, 0, 0) in component "BedFrame_ServiceDeck"
  line L0 (-44.5, -175.3) -> (-42.5, -175.3)
  line L1 (-42.5, -175.3) -> (-42.5, -149.3)
  line L2 (-42.5, -149.3) -> (-44.5, -149.3)
  line L3 (-44.5, -149.3) -> (-44.5, -175.3)
extrude "ValveRail_A1_-1" add sketch "ValveRail_A1_-1_Sketch" along normal blind 10.1 bodies 2 in component "BedFrame_ServiceDeck"
ref_plane "WorkPlane33" through (0, 0, 22) normal (0, 0, 1) x (1, 0, 0) in component "BedFrame_ServiceDeck"
sketch "ValveRail_A1_1_Sketch" plane through (0, 0, 22) normal (0, 0, 1) x (1, 0, 0) in component "BedFrame_ServiceDeck"
  line L0 (-29.5, -175.3) -> (-27.5, -175.3)
  line L1 (-27.5, -175.3) -> (-27.5, -149.3)
  line L2 (-27.5, -149.3) -> (-29.5, -149.3)
  line L3 (-29.5, -149.3) -> (-29.5, -175.3)
extrude "ValveRail_A1_1" add sketch "ValveRail_A1_1_Sketch" along normal blind 10.1 bodies 2 in component "BedFrame_ServiceDeck"
ref_plane "WorkPlane34" through (0, 0, 22) normal (0, 0, 1) x (1, 0, 0) in component "BedFrame_ServiceDeck"
sketch "ValveRail_B1_-1_Sketch" plane through (0, 0, 22) normal (0, 0, 1) x (1, 0, 0) in component "BedFrame_ServiceDeck"
  line L0 (-20.5, -175.3) -> (-18.5, -175.3)
  line L1 (-18.5, -175.3) -> (-18.5, -149.3)
  line L2 (-18.5, -149.3) -> (-20.5, -149.3)
  line L3 (-20.5, -149.3) -> (-20.5, -175.3)
extrude "ValveRail_B1_-1" add sketch "ValveRail_B1_-1_Sketch" along normal blind 10.1 bodies 2 in component "BedFrame_ServiceDeck"
ref_plane "WorkPlane35" through (0, 0, 22) normal (0, 0, 1) x (1, 0, 0) in component "BedFrame_ServiceDeck"
sketch "ValveRail_B1_1_Sketch" plane through (0, 0, 22) normal (0, 0, 1) x (1, 0, 0) in component "BedFrame_ServiceDeck"
  line L0 (-5.5, -175.3) -> (-3.5, -175.3)
  line L1 (-3.5, -175.3) -> (-3.5, -149.3)
  line L2 (-3.5, -149.3) -> (-5.5, -149.3)
  line L3 (-5.5, -149.3) -> (-5.5, -175.3)
extrude "ValveRail_B1_1" add sketch "ValveRail_B1_1_Sketch" along normal blind 10.1 bodies 2 in component "BedFrame_ServiceDeck"
ref_plane "WorkPlane36" through (0, 0, 22) normal (0, 0, 1) x (1, 0, 0) in component "BedFrame_ServiceDeck"
sketch "ValveRail_C1_-1_Sketch" plane through (0, 0, 22) normal (0, 0, 1) x (1, 0, 0) in component "BedFrame_ServiceDeck"
  line L0 (3.5, -175.3) -> (5.5, -175.3)
  line L1 (5.5, -175.3) -> (5.5, -149.3)
  line L2 (5.5, -149.3) -> (3.5, -149.3)
  line L3 (3.5, -149.3) -> (3.5, -175.3)
extrude "ValveRail_C1_-1" add sketch "ValveRail_C1_-1_Sketch" along normal blind 10.1 bodies 2 in component "BedFrame_ServiceDeck"
ref_plane "WorkPlane37" through (0, 0, 22) normal (0, 0, 1) x (1, 0, 0) in component "BedFrame_ServiceDeck"
sketch "ValveRail_C1_1_Sketch" plane through (0, 0, 22) normal (0, 0, 1) x (1, 0, 0) in component "BedFrame_ServiceDeck"
  line L0 (18.5, -175.3) -> (20.5, -175.3)
  line L1 (20.5, -175.3) -> (20.5, -149.3)
  line L2 (20.5, -149.3) -> (18.5, -149.3)
  line L3 (18.5, -149.3) -> (18.5, -175.3)
extrude "ValveRail_C1_1" add sketch "ValveRail_C1_1_Sketch" along normal blind 10.1 bodies 2 in component "BedFrame_ServiceDeck"
ref_plane "WorkPlane38" through (0, 0, 22) normal (0, 0, 1) x (1, 0, 0) in component "BedFrame_ServiceDeck"
sketch "ValveRail_A2_-1_Sketch" plane through (0, 0, 22) normal (0, 0, 1) x (1, 0, 0) in component "BedFrame_ServiceDeck"
  line L0 (27.5, -175.3) -> (29.5, -175.3)
  line L1 (29.5, -175.3) -> (29.5, -149.3)
  line L2 (29.5, -149.3) -> (27.5, -149.3)
  line L3 (27.5, -149.3) -> (27.5, -175.3)
extrude "ValveRail_A2_-1" add sketch "ValveRail_A2_-1_Sketch" along normal blind 10.1 bodies 2 in component "BedFrame_ServiceDeck"
ref_plane "WorkPlane39" through (0, 0, 22) normal (0, 0, 1) x (1, 0, 0) in component "BedFrame_ServiceDeck"
sketch "ValveRail_A2_1_Sketch" plane through (0, 0, 22) normal (0, 0, 1) x (1, 0, 0) in component "BedFrame_ServiceDeck"
  line L0 (42.5, -175.3) -> (44.5, -175.3)
  line L1 (44.5, -175.3) -> (44.5, -149.3)
  line L2 (44.5, -149.3) -> (42.5, -149.3)
  line L3 (42.5, -149.3) -> (42.5, -175.3)
extrude "ValveRail_A2_1" add sketch "ValveRail_A2_1_Sketch" along normal blind 10.1 bodies 2 in component "BedFrame_ServiceDeck"
ref_plane "WorkPlane40" through (0, 0, 22) normal (0, 0, 1) x (1, 0, 0) in component "BedFrame_ServiceDeck"
sketch "ValveRail_B2_-1_Sketch" plane through (0, 0, 22) normal (0, 0, 1) x (1, 0, 0) in component "BedFrame_ServiceDeck"
  line L0 (-44.5, -207.3) -> (-42.5, -207.3)
  line L1 (-42.5, -207.3) -> (-42.5, -181.3)
  line L2 (-42.5, -181.3) -> (-44.5, -181.3)
  line L3 (-44.5, -181.3) -> (-44.5, -207.3)
extrude "ValveRail_B2_-1" add sketch "ValveRail_B2_-1_Sketch" along normal blind 10.1 bodies 2 in component "BedFrame_ServiceDeck"
ref_plane "WorkPlane41" through (0, 0, 22) normal (0, 0, 1) x (1, 0, 0) in component "BedFrame_ServiceDeck"
sketch "ValveRail_B2_1_Sketch" plane through (0, 0, 22) normal (0, 0, 1) x (1, 0, 0) in component "BedFrame_ServiceDeck"
  line L0 (-29.5, -207.3) -> (-27.5, -207.3)
  line L1 (-27.5, -207.3) -> (-27.5, -181.3)
  line L2 (-27.5, -181.3) -> (-29.5, -181.3)
  line L3 (-29.5, -181.3) -> (-29.5, -207.3)
extrude "ValveRail_B2_1" add sketch "ValveRail_B2_1_Sketch" along normal blind 10.1 bodies 2 in component "BedFrame_ServiceDeck"
ref_plane "WorkPlane42" through (0, 0, 22) normal (0, 0, 1) x (1, 0, 0) in component "BedFrame_ServiceDeck"
sketch "ValveRail_C2_-1_Sketch" plane through (0, 0, 22) normal (0, 0, 1) x (1, 0, 0) in component "BedFrame_ServiceDeck"
  line L0 (-20.5, -207.3) -> (-18.5, -207.3)
  line L1 (-18.5, -207.3) -> (-18.5, -181.3)
  line L2 (-18.5, -181.3) -> (-20.5, -181.3)
  line L3 (-20.5, -181.3) -> (-20.5, -207.3)
extrude "ValveRail_C2_-1" add sketch "ValveRail_C2_-1_Sketch" along normal blind 10.1 bodies 2 in component "BedFrame_ServiceDeck"
ref_plane "WorkPlane43" through (0, 0, 22) normal (0, 0, 1) x (1, 0, 0) in component "BedFrame_ServiceDeck"
sketch "ValveRail_C2_1_Sketch" plane through (0, 0, 22) normal (0, 0, 1) x (1, 0, 0) in component "BedFrame_ServiceDeck"
  line L0 (-5.5, -207.3) -> (-3.5, -207.3)
  line L1 (-3.5, -207.3) -> (-3.5, -181.3)
  line L2 (-3.5, -181.3) -> (-5.5, -181.3)
  line L3 (-5.5, -181.3) -> (-5.5, -207.3)
extrude "ValveRail_C2_1" add sketch "ValveRail_C2_1_Sketch" along normal blind 10.1 bodies 2 in component "BedFrame_ServiceDeck"
ref_plane "WorkPlane44" through (0, 0, 22) normal (0, 0, 1) x (1, 0, 0) in component "BedFrame_ServiceDeck"
sketch "ValveRail_A3_-1_Sketch" plane through (0, 0, 22) normal (0, 0, 1) x (1, 0, 0) in component "BedFrame_ServiceDeck"
  line L0 (3.5, -207.3) -> (5.5, -207.3)
  line L1 (5.5, -207.3) -> (5.5, -181.3)
  line L2 (5.5, -181.3) -> (3.5, -181.3)
  line L3 (3.5, -181.3) -> (3.5, -207.3)
extrude "ValveRail_A3_-1" add sketch "ValveRail_A3_-1_Sketch" along normal blind 10.1 bodies 2 in component "BedFrame_ServiceDeck"
ref_plane "WorkPlane45" through (0, 0, 22) normal (0, 0, 1) x (1, 0, 0) in component "BedFrame_ServiceDeck"
sketch "ValveRail_A3_1_Sketch" plane through (0, 0, 22) normal (0, 0, 1) x (1, 0, 0) in component "BedFrame_ServiceDeck"
  line L0 (18.5, -207.3) -> (20.5, -207.3)
  line L1 (20.5, -207.3) -> (20.5, -181.3)
  line L2 (20.5, -181.3) -> (18.5, -181.3)
  line L3 (18.5, -181.3) -> (18.5, -207.3)
extrude "ValveRail_A3_1" add sketch "ValveRail_A3_1_Sketch" along normal blind 10.1 bodies 2 in component "BedFrame_ServiceDeck"
ref_plane "WorkPlane46" through (0, 0, 22) normal (0, 0, 1) x (1, 0, 0) in component "BedFrame_ServiceDeck"
sketch "ValveRail_B3_-1_Sketch" plane through (0, 0, 22) normal (0, 0, 1) x (1, 0, 0) in component "BedFrame_ServiceDeck"
  line L0 (27.5, -207.3) -> (29.5, -207.3)
  line L1 (29.5, -207.3) -> (29.5, -181.3)
  line L2 (29.5, -181.3) -> (27.5, -181.3)
  line L3 (27.5, -181.3) -> (27.5, -207.3)
extrude "ValveRail_B3_-1" add sketch "ValveRail_B3_-1_Sketch" along normal blind 10.1 bodies 2 in component "BedFrame_ServiceDeck"
ref_plane "WorkPlane47" through (0, 0, 22) normal (0, 0, 1) x (1, 0, 0) in component "BedFrame_ServiceDeck"
sketch "ValveRail_B3_1_Sketch" plane through (0, 0, 22) normal (0, 0, 1) x (1, 0, 0) in component "BedFrame_ServiceDeck"
  line L0 (42.5, -207.3) -> (44.5, -207.3)
  line L1 (44.5, -207.3) -> (44.5, -181.3)
  line L2 (44.5, -181.3) -> (42.5, -181.3)
  line L3 (42.5, -181.3) -> (42.5, -207.3)
extrude "ValveRail_B3_1" add sketch "ValveRail_B3_1_Sketch" along normal blind 10.1 bodies 2 in component "BedFrame_ServiceDeck"
ref_plane "WorkPlane48" through (0, 0, 22) normal (0, 0, 1) x (1, 0, 0) in component "BedFrame_ServiceDeck"
sketch "ValveRail_C3_-1_Sketch" plane through (0, 0, 22) normal (0, 0, 1) x (1, 0, 0) in component "BedFrame_ServiceDeck"
  line L0 (-44.5, -239.3) -> (-42.5, -239.3)
  line L1 (-42.5, -239.3) -> (-42.5, -213.3)
  line L2 (-42.5, -213.3) -> (-44.5, -213.3)
  line L3 (-44.5, -213.3) -> (-44.5, -239.3)
extrude "ValveRail_C3_-1" add sketch "ValveRail_C3_-1_Sketch" along normal blind 10.1 bodies 2 in component "BedFrame_ServiceDeck"
ref_plane "WorkPlane49" through (0, 0, 22) normal (0, 0, 1) x (1, 0, 0) in component "BedFrame_ServiceDeck"
sketch "ValveRail_C3_1_Sketch" plane through (0, 0, 22) normal (0, 0, 1) x (1, 0, 0) in component "BedFrame_ServiceDeck"
  line L0 (-29.5, -239.3) -> (-27.5, -239.3)
  line L1 (-27.5, -239.3) -> (-27.5, -213.3)
  line L2 (-27.5, -213.3) -> (-29.5, -213.3)
  line L3 (-29.5, -213.3) -> (-29.5, -239.3)
extrude "ValveRail_C3_1" add sketch "ValveRail_C3_1_Sketch" along normal blind 10.1 bodies 2 in component "BedFrame_ServiceDeck"
ref_plane "WorkPlane50" through (0, 0, 22) normal (0, 0, 1) x (1, 0, 0) in component "BedFrame_ServiceDeck"
sketch "ValveRail_A4_-1_Sketch" plane through (0, 0, 22) normal (0, 0, 1) x (1, 0, 0) in component "BedFrame_ServiceDeck"
  line L0 (-20.5, -239.3) -> (-18.5, -239.3)
  line L1 (-18.5, -239.3) -> (-18.5, -213.3)
  line L2 (-18.5, -213.3) -> (-20.5, -213.3)
  line L3 (-20.5, -213.3) -> (-20.5, -239.3)
extrude "ValveRail_A4_-1" add sketch "ValveRail_A4_-1_Sketch" along normal blind 10.1 bodies 2 in component "BedFrame_ServiceDeck"
ref_plane "WorkPlane51" through (0, 0, 22) normal (0, 0, 1) x (1, 0, 0) in component "BedFrame_ServiceDeck"
sketch "ValveRail_A4_1_Sketch" plane through (0, 0, 22) normal (0, 0, 1) x (1, 0, 0) in component "BedFrame_ServiceDeck"
  line L0 (-5.5, -239.3) -> (-3.5, -239.3)
  line L1 (-3.5, -239.3) -> (-3.5, -213.3)
  line L2 (-3.5, -213.3) -> (-5.5, -213.3)
  line L3 (-5.5, -213.3) -> (-5.5, -239.3)
extrude "ValveRail_A4_1" add sketch "ValveRail_A4_1_Sketch" along normal blind 10.1 bodies 2 in component "BedFrame_ServiceDeck"
ref_plane "WorkPlane52" through (0, 0, 22) normal (0, 0, 1) x (1, 0, 0) in component "BedFrame_ServiceDeck"
sketch "ValveRail_B4_-1_Sketch" plane through (0, 0, 22) normal (0, 0, 1) x (1, 0, 0) in component "BedFrame_ServiceDeck"
  line L0 (3.5, -239.3) -> (5.5, -239.3)
  line L1 (5.5, -239.3) -> (5.5, -213.3)
  line L2 (5.5, -213.3) -> (3.5, -213.3)
  line L3 (3.5, -213.3) -> (3.5, -239.3)
extrude "ValveRail_B4_-1" add sketch "ValveRail_B4_-1_Sketch" along normal blind 10.1 bodies 2 in component "BedFrame_ServiceDeck"
ref_plane "WorkPlane53" through (0, 0, 22) normal (0, 0, 1) x (1, 0, 0) in component "BedFrame_ServiceDeck"
sketch "ValveRail_B4_1_Sketch" plane through (0, 0, 22) normal (0, 0, 1) x (1, 0, 0) in component "BedFrame_ServiceDeck"
  line L0 (18.5, -239.3) -> (20.5, -239.3)
  line L1 (20.5, -239.3) -> (20.5, -213.3)
  line L2 (20.5, -213.3) -> (18.5, -213.3)
  line L3 (18.5, -213.3) -> (18.5, -239.3)
extrude "ValveRail_B4_1" add sketch "ValveRail_B4_1_Sketch" along normal blind 10.1 bodies 2 in component "BedFrame_ServiceDeck"
ref_plane "WorkPlane54" through (0, 0, 22) normal (0, 0, 1) x (1, 0, 0) in component "BedFrame_ServiceDeck"
sketch "ValveRail_C4_-1_Sketch" plane through (0, 0, 22) normal (0, 0, 1) x (1, 0, 0) in component "BedFrame_ServiceDeck"
  line L0 (27.5, -239.3) -> (29.5, -239.3)
  line L1 (29.5, -239.3) -> (29.5, -213.3)
  line L2 (29.5, -213.3) -> (27.5, -213.3)
  line L3 (27.5, -213.3) -> (27.5, -239.3)
extrude "ValveRail_C4_-1" add sketch "ValveRail_C4_-1_Sketch" along normal blind 10.1 bodies 2 in component "BedFrame_ServiceDeck"
ref_plane "WorkPlane55" through (0, 0, 22) normal (0, 0, 1) x (1, 0, 0) in component "BedFrame_ServiceDeck"
sketch "ValveRail_C4_1_Sketch" plane through (0, 0, 22) normal (0, 0, 1) x (1, 0, 0) in component "BedFrame_ServiceDeck"
  line L0 (42.5, -239.3) -> (44.5, -239.3)
  line L1 (44.5, -239.3) -> (44.5, -213.3)
  line L2 (44.5, -213.3) -> (42.5, -213.3)
  line L3 (42.5, -213.3) -> (42.5, -239.3)
extrude "ValveRail_C4_1" add sketch "ValveRail_C4_1_Sketch" along normal blind 10.1 bodies 2 in component "BedFrame_ServiceDeck"
fillet "OuterTopEdgeSoftening'" radius 0.6 8 edges at (0, -262.3, 36) (0, -126.3, 36) (-102.2426, -128.0574, 36) (102.2426, -128.0574, 36) (104, -194.3, 36) (102.2426, -260.5426, 36) (-102.2426, -260.5426, 36) (-104, -194.3, 36) on bodies 2 in component "BedFrame_ServiceDeck"
ref_plane "WorkPlane1" through (0, 0, -52) normal (0, 0, 1) x (1, 0, 0) in component "BedFrame_ElectronicsBay"
sketch "BayBlank_Sketch" plane through (0, 0, -52) normal (0, 0, 1) x (1, 0, 0) in component "BedFrame_ElectronicsBay"
  line L0 (-104, -262.3) -> (104, -262.3)
  line L1 (104, -262.3) -> (104, -126.3)
  line L2 (104, -126.3) -> (-104, -126.3)
  line L3 (-104, -126.3) -> (-104, -262.3)
extrude "BayBlank" add sketch "BayBlank_Sketch" along normal blind 52 separate body makes body 3 in component "BedFrame_ElectronicsBay"
fillet "BayCorners" radius 6 4 edges at (-104, -126.3, -26) (104, -126.3, -26) (104, -262.3, -26) (-104, -262.3, -26) on bodies 3 in component "BedFrame_ElectronicsBay"
ref_plane "WorkPlane2" through (0, 0, -52.1) normal (0, 0, 1) x (1, 0, 0) in component "BedFrame_ElectronicsBay"
sketch "BayOpenBothSides_Sketch" plane through (0, 0, -52.1) normal (0, 0, 1) x (1, 0, 0) in component "BedFrame_ElectronicsBay"
  line L0 (-100, -258.3) -> (100, -258.3)
  line L1 (100, -258.3) -> (100, -130.3)
  line L2 (100, -130.3) -> (-100, -130.3)
  line L3 (-100, -130.3) -> (-100, -258.3)
extrude "BayOpenBothSides" cut sketch "BayOpenBothSides_Sketch" along normal blind 52.2 bodies 3 in component "BedFrame_ElectronicsBay"
ref_plane "WorkPlane3" through (0, 0, -4) normal (0, 0, 1) x (1, 0, 0) in component "BedFrame_ElectronicsBay"
sketch "UpperFlangeBlank_Sketch" plane through (0, 0, -4) normal (0, 0, 1) x (1, 0, 0) in component "BedFrame_ElectronicsBay"
  line L0 (-100.1, -258.4) -> (100.1, -258.4)
  line L1 (100.1, -258.4) -> (100.1, -130.2)
  line L2 (100.1, -130.2) -> (-100.1, -130.2)
  line L3 (-100.1, -130.2) -> (-100.1, -258.4)
extrude "UpperFlangeBlank" add sketch "UpperFlangeBlank_Sketch" along normal blind 4 bodies 3 in component "BedFrame_ElectronicsBay"
ref_plane "WorkPlane4" through (0, 0, -4.1) normal (0, 0, 1) x (1, 0, 0) in component "BedFrame_ElectronicsBay"
sketch "UpperFlangeOpening_Sketch" plane through (0, 0, -4.1) normal (0, 0, 1) x (1, 0, 0) in component "BedFrame_ElectronicsBay"
  line L0 (-94, -252.3) -> (94, -252.3)
  line L1 (94, -252.3) -> (94, -136.3)
  line L2 (94, -136.3) -> (-94, -136.3)
  line L3 (-94, -136.3) -> (-94, -252.3)
extrude "UpperFlangeOpening" cut sketch "UpperFlangeOpening_Sketch" along normal blind 4.2 bodies 3 in component "BedFrame_ElectronicsBay"
ref_plane "WorkPlane5" through (0, 0, -4.1) normal (0, 0, 1) x (1, 0, 0) in component "BedFrame_ElectronicsBay"
sketch "UpperClearance_0_Sketch" plane through (0, 0, -4.1) normal (0, 0, 1) x (1, 0, 0) in component "BedFrame_ElectronicsBay"
  circle A0 centre (-97, -255.3) radius 1.35
extrude "UpperClearance_0" cut sketch "UpperClearance_0_Sketch" along normal blind 4.2 bodies 3 in component "BedFrame_ElectronicsBay"
ref_plane "WorkPlane6" through (0, 0, -52) normal (0, 0, 1) x (1, 0, 0) in component "BedFrame_ElectronicsBay"
sketch "LowerWebX_0_Sketch" plane through (0, 0, -52) normal (0, 0, 1) x (1, 0, 0) in component "BedFrame_ElectronicsBay"
  line L0 (-103.9, -256.3) -> (-97, -256.3)
  line L1 (-97, -256.3) -> (-97, -254.3)
  line L2 (-97, -254.3) -> (-103.9, -254.3)
  line L3 (-103.9, -254.3) -> (-103.9, -256.3)
extrude "LowerWebX_0" add sketch "LowerWebX_0_Sketch" along normal blind 8 bodies 3 in component "BedFrame_ElectronicsBay"
ref_plane "WorkPlane7" through (0, 0, -52) normal (0, 0, 1) x (1, 0, 0) in component "BedFrame_ElectronicsBay"